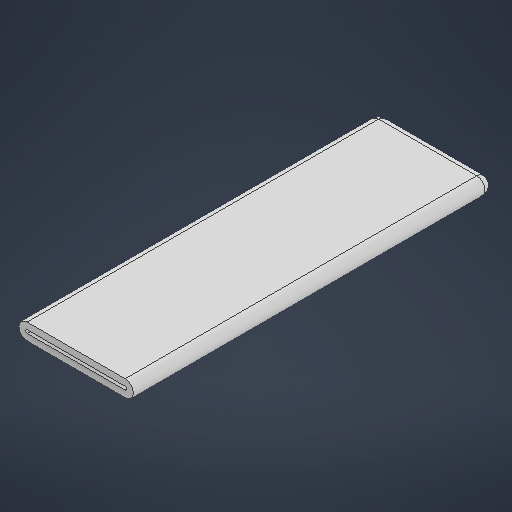
# Autodesk Inventor part: Back Pillar
Saved by Autodesk Inventor 2025.2 (Build 292293000, 293)
## iProperties
Created: 2025-01-18
Part Number: Back Pillar
Material: Generic
Document SubType Name: Modeling
Designer: user
Density: 1 g/cm^3
Appearance: Default
Author: user
Autodesk Inventor part; units mm, degrees
ref_plane "YZ Plane" through (0, 0, 0) normal (1, 0, 0) x (0, 1, 0)
ref_plane "XZ Plane" through (0, 0, 0) normal (0, 1, 0) x (-1, 0, 0)
ref_plane "XY Plane" through (0, 0, 0) normal (0, 0, 1) x (1, 0, 0)
sketch "Sketch1" plane through (0, 0, 0) normal (0, 0, 1) x (1, 0, 0)
  line L0 (-150, 0) -> (150, 0) construction
  line L1 (-150, -25) -> (150, -25)
  line L2 (150, 25) -> (-150, 25)
  arc A0 (-150, 25) -> (-150, -25) centre (-150, 0) ccw
  arc A1 (150, -25) -> (150, 25) centre (150, 0) ccw
  line L3 (-150, -5) -> (150, -5)
  arc A2 (150, -5) -> (150, 5) centre (150, 0) ccw
  line L4 (150, 5) -> (-150, 5)
  arc A3 (-150, 5) -> (-150, -5) centre (-150, 0) ccw
  point P0 (0, 0)
  dimension "d0" = 150
  dimension "d1" = 50
  dimension "d2" = 20
  constraints: 12 end point, 8 point on circle, 4 centre point, 4 tangent, 2 parallel, 1 horizontal, 1 midpoint, 3 other
  measures "d0" distance of point (0, 0) L0.end
  measures "d1" diameter of A1
  measures "d2" radial gap between concentric circles of A0 A3
extrude "Extrusion1" add sketch "Sketch1" along normal blind 1000
sketch "Sketch2" plane through (0, 0, 0) normal (0, 0, -1) x (-1, 0, 0)
  arc A0 (-150, 5) -> (-150, -5) centre (-150, 0) ccw projected
  line L0 (150, 0) -> (-150, 0) construction
  arc A1 (150, -25) -> (150, 25) centre (150, 0) ccw projected
  line L1 (150, -25) -> (-150, -25) projected
  arc A2 (-150, 25) -> (-150, -25) centre (-150, 0) ccw projected
  line L2 (-150, 25) -> (150, 25) projected
  point P0 (0, 0)
  constraints: 4 end point, 1 horizontal, 1 midpoint
extrude "Extrusion4" add sketch "Sketch2" along normal blind 100
fillet "Fillet3" radius 25 4 edges at (175, 0, -100) (0, -25, -100) (-175, 0, -100) (0, 25, -100)
body "Solid1"
